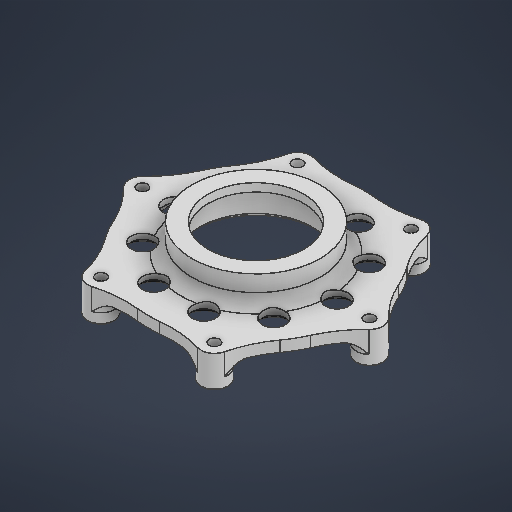
# Autodesk Inventor part: casing
Saved by Autodesk Inventor 2026.2 (Build 302298010, 298A)
## iProperties
Created: 2026-04-07
Part Number: casing
Material: 일반
Document SubType Name: Modeling
Designer: work
Density: 1 g/cm^3
Appearance: 기본값
Author: work
Autodesk Inventor part; units mm, degrees
ref_plane "YZ Plane" through (0, 0, 0) normal (1, 0, 0) x (0, 1, 0)
ref_plane "XZ Plane" through (0, 0, 0) normal (0, 1, 0) x (-1, 0, 0)
ref_plane "XY Plane" through (0, 0, 0) normal (0, 0, 1) x (1, 0, 0)
sketch "스케치1" plane through (0, 0, 0) normal (0, 1, 0) x (-1, 0, 0)
  circle A0 centre (0, 0) radius 42 construction
  line L0 (0, 0) -> (42, 0) construction
  circle A1 centre (42, 0) radius 2
  circle A2 centre (30, 0) radius 4.25
  circle A3 centre (24.2705, 17.6336) radius 4.25
  circle A4 centre (9.2705, 28.5317) radius 4.25
  circle A5 centre (-9.2705, 28.5317) radius 4.25
  circle A6 centre (-24.2705, 17.6336) radius 4.25
  circle A7 centre (-30, 0) radius 4.25
  circle A8 centre (-24.2705, -17.6336) radius 4.25
  circle A9 centre (-9.2705, -28.5317) radius 4.25
  circle A10 centre (9.2705, -28.5317) radius 4.25
  circle A11 centre (24.2705, -17.6336) radius 4.25
  circle A12 centre (42, 0) radius 5
  circle A13 centre (0, 0) radius 20.7
  circle A14 centre (0, 0) radius 40
  arc A15 (36.5417, 16.2698) -> (45.4537, 3.6155) centre (73.0833, 32.5396) ccw
  arc A16 (45.4537, -3.6155) -> (36.5417, -16.2698) centre (73.0833, -32.5396) ccw
  arc A17 (25.858, 37.5563) -> (32.3609, 23.5111) centre (64.7218, 47.0222) ccw
  circle A18 centre (21, 36.3731) radius 2
  circle A19 centre (21, 36.3731) radius 5
  arc A20 (4.1808, 39.7809) -> (19.5957, 41.1718) centre (8.3615, 79.5618) ccw
  arc A21 (-19.5957, 41.1718) -> (-4.1808, 39.7809) centre (-8.3615, 79.5618) ccw
  circle A22 centre (-21, 36.3731) radius 2
  circle A23 centre (-21, 36.3731) radius 5
  arc A24 (-32.3609, 23.5111) -> (-25.858, 37.5563) centre (-64.7218, 47.0222) ccw
  arc A25 (-45.4537, 3.6155) -> (-36.5417, 16.2698) centre (-73.0833, 32.5396) ccw
  circle A26 centre (-42, 0) radius 2
  circle A27 centre (-42, 0) radius 5
  arc A28 (-36.5417, -16.2698) -> (-45.4537, -3.6155) centre (-73.0833, -32.5396) ccw
  arc A29 (-25.858, -37.5563) -> (-32.3609, -23.5111) centre (-64.7218, -47.0222) ccw
  circle A30 centre (-21, -36.3731) radius 2
  circle A31 centre (-21, -36.3731) radius 5
  arc A32 (-4.1808, -39.7809) -> (-19.5957, -41.1718) centre (-8.3615, -79.5618) ccw
  arc A33 (19.5957, -41.1718) -> (4.1808, -39.7809) centre (8.3615, -79.5618) ccw
  circle A34 centre (21, -36.3731) radius 2
  circle A35 centre (21, -36.3731) radius 5
  arc A36 (32.3609, -23.5111) -> (25.858, -37.5563) centre (64.7218, -47.0222) ccw
  point P0 (32.3609, 23.5111)
  point P1 (-4.1808, 39.7809)
  point P2 (-36.5417, 16.2698)
  point P3 (-45.4537, 3.6155)
  point P4 (-32.3609, -23.5111)
  point P5 (-4.1808, -39.7809)
  point P6 (4.1808, -39.7809)
  point P7 (19.5957, -41.1718)
  point P8 (36.5417, -16.2698)
  point P9 (45.4537, -3.6155)
  dimension "d0" = 84
  dimension "d8" = 10
  dimension "d10" = 80
  dimension "d1" = 4
  dimension "d2" = 8.5
  dimension "d3" = 30
  dimension "d6" = 360
  dimension "d9" = 41.4
  dimension "d11" = 40
  dimension "d14" = 360
  constraints: 29 centre point, 24 point on circle, 10 coincident, 3 symmetric about line, 2 end point, 1 horizontal, 1 horizontal alignment, 1 point on line, 120 other
  measures "d1" diameter of A1
  measures "d2" diameter of A2
  measures "d3" distance of point (0, 0) A2.centre
  measures "d9" diameter of A13
  measures "d11" radius of A15
extrude "돌출1" add sketch "스케치1" along normal blind 4
sketch "스케치2" plane through (0, 0, 0) normal (0, -1, 0) x (1, 0, 0)
  arc A0 (-32.3609, 23.5111) -> (-36.5417, 16.2698) centre (0, 0) ccw projected
  arc A1 (-45.4537, 3.6155) -> (-36.5417, 16.2698) centre (-73.0833, 32.5396) ccw projected
  arc A2 (-45.4537, 3.6155) -> (-45.4537, -3.6155) centre (-42, 0) ccw projected
  arc A3 (-36.5417, -16.2698) -> (-45.4537, -3.6155) centre (-73.0833, -32.5396) ccw projected
  arc A4 (-36.5417, -16.2698) -> (-32.3609, -23.5111) centre (0, 0) ccw projected
  arc A5 (-25.858, -37.5563) -> (-32.3609, -23.5111) centre (-64.7218, -47.0222) ccw projected
  arc A6 (-25.858, -37.5563) -> (-19.5957, -41.1718) centre (-21, -36.3731) ccw projected
  arc A7 (-4.1808, -39.7809) -> (-19.5957, -41.1718) centre (-8.3615, -79.5618) ccw projected
  arc A8 (-4.1808, -39.7809) -> (4.1808, -39.7809) centre (0, 0) ccw projected
  arc A9 (19.5957, -41.1718) -> (4.1808, -39.7809) centre (8.3615, -79.5618) ccw projected
  arc A10 (19.5957, -41.1718) -> (25.858, -37.5563) centre (21, -36.3731) ccw projected
  arc A11 (32.3609, -23.5111) -> (25.858, -37.5563) centre (64.7218, -47.0222) ccw projected
  arc A12 (32.3609, -23.5111) -> (36.5417, -16.2698) centre (0, 0) ccw projected
  arc A13 (45.4537, -3.6155) -> (36.5417, -16.2698) centre (73.0833, -32.5396) ccw projected
  arc A14 (45.4537, -3.6155) -> (45.4537, 3.6155) centre (42, 0) ccw projected
  arc A15 (36.5417, 16.2698) -> (45.4537, 3.6155) centre (73.0833, 32.5396) ccw projected
  arc A16 (36.5417, 16.2698) -> (32.3609, 23.5111) centre (0, 0) ccw projected
  arc A17 (25.858, 37.5563) -> (32.3609, 23.5111) centre (64.7218, 47.0222) ccw projected
  arc A18 (25.858, 37.5563) -> (19.5957, 41.1718) centre (21, 36.3731) ccw projected
  arc A19 (4.1808, 39.7809) -> (19.5957, 41.1718) centre (8.3615, 79.5618) ccw projected
  arc A20 (4.1808, 39.7809) -> (-4.1808, 39.7809) centre (0, 0) ccw projected
  arc A21 (-19.5957, 41.1718) -> (-4.1808, 39.7809) centre (-8.3615, 79.5618) ccw projected
  arc A22 (-19.5957, 41.1718) -> (-25.858, 37.5563) centre (-21, 36.3731) ccw projected
  arc A23 (-32.3609, 23.5111) -> (-25.858, 37.5563) centre (-64.7218, 47.0222) ccw projected
  circle A24 centre (21, 36.3731) radius 2 projected
  circle A25 centre (21, -36.3731) radius 2 projected
  circle A26 centre (-30, 0) radius 4.25 projected
  circle A27 centre (-24.2705, 17.6336) radius 4.25 projected
  circle A28 centre (-9.2705, 28.5317) radius 4.25 projected
  circle A29 centre (9.2705, 28.5317) radius 4.25 projected
  circle A30 centre (24.2705, 17.6336) radius 4.25 projected
  circle A31 centre (30, 0) radius 4.25 projected
  circle A32 centre (24.2705, -17.6336) radius 4.25 projected
  circle A33 centre (9.2705, -28.5317) radius 4.25 projected
  circle A34 centre (-9.2705, -28.5317) radius 4.25 projected
  circle A35 centre (-24.2705, -17.6336) radius 4.25 projected
  circle A36 centre (0, 0) radius 20.7 projected
  circle A37 centre (-21, -36.3731) radius 2 projected
  circle A38 centre (42, 0) radius 2 projected
  circle A39 centre (-21, 36.3731) radius 2 projected
  circle A40 centre (-42, 0) radius 2 projected
  circle A41 centre (-21, 36.3731) radius 5
  point P0 (-25.858, 37.5563)
  point P1 (-19.5957, 41.1718)
  constraints: 1 centre point, 1 coincident, 1 concentric
extrude "돌출2" add sketch "스케치2" along normal blind 8 contours A22 A41
pattern_circular "원형 패턴1" count 6 over 360 about axis through (0, -10, 0) along (0, 1, 0) of "돌출2"
fillet "모깎기1" radius 4 6 edges at (-18.5, 0, 32.0429) (-37, 0, 0) (-18.5, 0, -32.0429) (18.5, 0, -32.0429) (37, 0, 0) (18.5, 0, 32.0429)
chamfer "모따기1" distance 0.5 angle 45 12 edges at (-18.5, -8, 32.0429) (-23.5, -8, 40.7032) (18.5, -8, 32.0429) (23.5, -8, 40.7032) (-37, -8, 0) (-47, -8, 0) (-18.5, -8, -32.0429) (-23.5, -8, -40.7032) (18.5, -8, -32.0429) (23.5, -8, -40.7032) (37, -8, 0) (47, -8, 0)
sketch "스케치3" plane through (0, 4, 0) normal (0, 1, 0) x (1, 0, 0)
  circle A0 centre (0, 0) radius 23.7
  circle A1 centre (0, 0) radius 20.7 projected
  dimension "d27" = 3
  constraints: 1 centre point, 1 coincident
  measures "d27" radial gap between concentric circles of A0 A1
extrude "돌출3" add sketch "스케치3" along normal blind 7
fillet "모깎기2" radius 4 1 edges at (-23.7, 4, 0)
chamfer "모따기2" distance 2 angle 45 1 edges at (20.7, 0, 0)
chamfer "모따기3" distance 2 angle 45 14 edges at (28.6384, 0, 4.026) (28.6384, 0, -4.026) (34.25, -0.2003, 0) (28.5205, 0, -17.6336) (13.5205, 0, -28.5317) (-5.0205, 0, -28.5317) (-20.0205, 0, -17.6336) (-25.75, 0, 0) (-34.0242, -0.1044, 1.3669) (-34.0242, -0.1044, -1.3669) (-20.0205, 0, 17.6336) (-5.0205, 0, 28.5317) (13.5205, 0, 28.5317) (28.5205, 0, 17.6336)
sketch "스케치4" plane through (0, 11, 0) normal (0, 1, 0) x (1, 0, 0)
  circle A0 centre (0, 0) radius 23.7 projected
  circle A1 centre (0, 0) radius 20.7 projected
  circle A2 centre (0, 0) radius 17.7
  dimension "d37" = 3
  constraints: 1 centre point, 1 coincident
  measures "d37" radial gap between concentric circles of A1 A2
extrude "돌출4" add sketch "스케치4" along normal blind 3 contours A0 | A1
